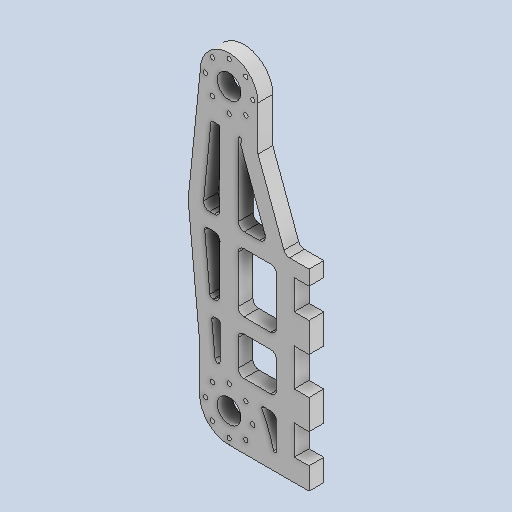
# Autodesk Inventor part: CalfSideL
Saved by Autodesk Inventor 2025.2 (Build 292293000, 293)
## iProperties
Created: 2025-06-24
Part Number: CalfSideL
Material: Generic
Document SubType Name: Modeling
Designer: ricoa
Density: 1 g/cm^3
Appearance: Default
Author: ricoa
Autodesk Inventor part; units mm, degrees
ref_plane "YZ Plane" through (0, 0, 0) normal (1, 0, 0) x (0, 1, 0)
ref_plane "XZ Plane" through (0, 0, 0) normal (0, 1, 0) x (-1, 0, 0)
ref_plane "XY Plane" through (0, 0, 0) normal (0, 0, 1) x (1, 0, 0)
sketch "Sketch1" plane through (0, 0, 0) normal (0, 0, 1) x (1, 0, 0)
  line L0 (-1.9363, -53.8484) -> (-0.1341, -49.1844) construction
  line L1 (-13.3705, 26.1501) -> (9.4827, 17.3195) construction
  circle A0 centre (0, 0) radius 4 projected
  circle A1 centre (-5.6569, 5.6569) radius 0.75 projected
  circle A2 centre (-8, 0) radius 0.75 projected
  circle A3 centre (-5.6569, -5.6569) radius 0.75 projected
  circle A4 centre (0, -8) radius 0.75 projected
  circle A5 centre (5.6569, -5.6569) radius 0.75 projected
  circle A6 centre (8, 0) radius 0.75 projected
  circle A7 centre (5.6569, 5.6569) radius 0.75 projected
  circle A8 centre (0, 8) radius 0.75 projected
  line L2 (0, 0) -> (0, -10)
  line L3 (75.6727, -5.2019) -> (75.6727, 49.7974) projected
  arc A9 (9.75, 94.9743) -> (-9.75, 95.0257) centre (0, 95) ccw
  circle A10 centre (0, 95) radius 4 projected
  circle A11 centre (-5.6569, 100.6569) radius 0.75 projected
  circle A12 centre (-8, 95) radius 0.75 projected
  circle A13 centre (-5.6569, 89.3431) radius 0.75 projected
  circle A14 centre (0, 87) radius 0.75 projected
  circle A15 centre (5.6569, 89.3431) radius 0.75 projected
  circle A16 centre (8, 95) radius 0.75 projected
  circle A17 centre (5.6569, 100.6569) radius 0.75 projected
  circle A18 centre (0, 103) radius 0.75 projected
  arc A19 (-9.9999, 0.0526) -> (0, -10) centre (0, 0) ccw
  line L4 (-10, 0) -> (-9.75, 95.0257) construction
  line L5 (-10, 0) -> (-9.9605, 14.9999)
  line L6 (9.75, 95.0257) -> (9.75, 80.4282)
  line L7 (-9.8553, 55) -> (-13.8553, 55) construction
  line L8 (-9.75, 95.0257) -> (-13.8349, 55.1989)
  line L9 (-13.8359, 54.801) -> (-9.9605, 14.9999)
  arc A20 (-13.8349, 55.1989) -> (-13.8359, 54.801) centre (-11.8453, 54.9948) ccw
  line L10 (0, -10) -> (15, -10)
  line L11 (15, -10) -> (27, -10)
  line L12 (27, -10) -> (27, 55)
  line L13 (27, 55) -> (20.393, 55)
  line L14 (9.75, 80.4282) -> (9.75, 80.0257)
  line L15 (18.517, 56.3066) -> (9.75, 80.0257)
  arc A21 (18.517, 56.3066) -> (20.393, 55) centre (20.393, 57) ccw
  line L16 (27, 55) -> (27, 50)
  line L17 (27, 50) -> (22, 50)
  line L18 (22, 50) -> (22, 40)
  line L19 (22, 40) -> (27, 40)
  line L20 (27, 40) -> (27, 30)
  line L21 (27, 30) -> (22, 30)
  line L22 (22, 30) -> (22, 17.4303)
  line L23 (22, 17.4303) -> (22, 27.4303)
  line L24 (22, 17.4303) -> (27, 17.4303)
  line L25 (27, 17.4303) -> (27, 7.4303)
  line L26 (27, 7.4303) -> (22, 7.4303)
  line L27 (22, 7.4303) -> (22, -2.5697)
  line L28 (22, -2.5697) -> (27, -2.5697)
  point P0 (19, 55)
  dimension "d20" = 10
  dimension "d22" = 15
  dimension "d23" = 15
  dimension "d25" = 4
  dimension "d27" = 15
  dimension "d28" = 12
  dimension "d29" = 65
  dimension "d30" = 8
  dimension "d31" = 2
  dimension "d32" = 5
  dimension "d33" = 5
  dimension "d34" = 10
  dimension "d35" = 10
  dimension "d36" = 10
  dimension "d37" = 10
  dimension "d38" = 10
  constraints: 52 end point, 19 point on line, 10 point on circle, 8 perpendicular, 5 tangent, 4 centre point, 4 vertical, 3 horizontal, 1 coincident
  measures "d20" distance of L2.start L2.end
  measures "d22" distance of L4.start L5.end
  measures "d23" distance of L6.start L14.end
  measures "d25" distance of L7.start L7.end
  measures "d27" distance of L2.end L10.end
  measures "d28" distance of L10.end L11.end
  measures "d29" distance of L11.end L12.end
  measures "d30" distance of L12.end point (19, 55)
  measures "d31" radius of A21
  measures "d32" distance of L12.end L16.end
  measures "d33" distance of L16.end L17.end
  measures "d34" distance of L17.end L18.end
  measures "d35" distance of L19.end L20.end
  measures "d36" distance of L22.end L23.end
  measures "d37" distance of L24.end L25.end
  measures "d38" distance of L26.end L27.end
extrude "Extrusion1" add sketch "Sketch1" along normal blind 5 contours L6 L14 L15 A21 L13 L12 L17 L18 L19 L21 L22 L24 L26 L27 L28 L11 L10 A19 L5 L9 A20 L8 A9
sketch "Sketch2" plane through (0, 0, 5) normal (0, 0, 1) x (1, 0, 0)
  line L0 (0, -10) -> (27, -10) projected
  line L1 (27, -10) -> (27, -2.5697) projected
  line L2 (27, -2.5697) -> (22, -2.5697) projected
  line L3 (22, -2.5697) -> (22, 7.4303) projected
  line L4 (22, 7.4303) -> (27, 7.4303) projected
  line L5 (27, 7.4303) -> (27, 17.4303) projected
  line L6 (27, 17.4303) -> (22, 17.4303) projected
  line L7 (22, 17.4303) -> (22, 30) projected
  line L8 (22, 30) -> (27, 30) projected
  line L9 (27, 30) -> (27, 40) projected
  line L10 (27, 40) -> (22, 40) projected
  line L11 (22, 40) -> (22, 50) projected
  line L12 (22, 50) -> (27, 50) projected
  line L13 (27, 50) -> (27, 55) projected
  line L14 (27, 55) -> (20.393, 55) projected
  arc A0 (18.517, 56.3066) -> (20.393, 55) centre (20.393, 57) ccw projected
  line L15 (18.517, 56.3066) -> (9.75, 80.0257) projected
  line L16 (9.75, 80.0257) -> (9.75, 95.0257) projected
  arc A1 (9.75, 95.0257) -> (-9.75, 95.0257) centre (0, 95) ccw projected
  line L17 (-9.75, 95.0257) -> (-13.8349, 55.1989) projected
  arc A2 (-13.8349, 55.1989) -> (-13.8359, 54.801) centre (-11.8453, 54.9948) ccw projected
  line L18 (-13.8359, 54.801) -> (-9.9605, 14.9999) projected
  line L19 (-9.9605, 14.9999) -> (-10, 0) projected
  arc A3 (-10, 0) -> (0, -10) centre (0, 0) ccw projected
  circle A4 centre (0, 0) radius 4 projected
  circle A5 centre (0, -8) radius 0.75 projected
  circle A6 centre (0, 87) radius 0.75 projected
  circle A7 centre (-5.6569, 5.6569) radius 0.75 projected
  circle A8 centre (5.6569, -5.6569) radius 0.75 projected
  circle A9 centre (8, 0) radius 0.75 projected
  circle A10 centre (5.6569, 5.6569) radius 0.75 projected
  circle A11 centre (0, 8) radius 0.75 projected
  circle A12 centre (-5.6569, 89.3431) radius 0.75 projected
  circle A13 centre (5.6569, 89.3431) radius 0.75 projected
  circle A14 centre (0, 103) radius 0.75 projected
  circle A15 centre (5.6569, 100.6569) radius 0.75 projected
  circle A16 centre (8, 95) radius 0.75 projected
  circle A17 centre (-8, 95) radius 0.75 projected
  circle A18 centre (-5.6569, 100.6569) radius 0.75 projected
  circle A19 centre (0, 95) radius 4 projected
  circle A20 centre (-5.6569, -5.6569) radius 0.75 projected
  circle A21 centre (-8, 0) radius 0.75 projected
  line L20 (3.9336, 79.8158) -> (12.1125, 57.6882)
  line L21 (10.2365, 54.9948) -> (5.108, 54.9948)
  line L22 (3.108, 56.9948) -> (3.108, 81.481)
  line L23 (4.1052, 81.4281) -> (3.9336, 79.8158)
  arc A22 (10.2365, 54.9948) -> (12.1125, 57.6882) centre (10.2365, 56.9948) ccw
  arc A23 (3.108, 56.9948) -> (5.108, 54.9948) centre (5.108, 56.9948) ccw
  arc A24 (4.1052, 81.4281) -> (3.108, 81.481) centre (3.608, 81.481) ccw
  line L24 (0, 87) -> (0, 0) construction
  line L25 (-9.75, 95.0257) -> (-13.8349, 55.1989) projected
  line L26 (-11.2885, 80.0257) -> (-6.2885, 80.0257)
  line L27 (-6.2885, 80.0257) -> (-8.6507, 56.9948)
  line L28 (-8.6507, 56.9948) -> (-8.6297, 57.1989)
  line L29 (-3.108, 56.9948) -> (-3.108, 81.481)
  line L30 (-3.108, 56.9948) -> (-3.108, 54.9948)
  line L31 (5.108, 54.9948) -> (3.108, 54.9948)
  line L32 (-5.108, 54.9948) -> (-6.6402, 54.9948)
  line L33 (-6.2885, 80.0257) -> (-6.1352, 81.5197)
  line L34 (-3.3913, 81.9687) -> (-5.6378, 81.9687)
  arc A25 (-5.6378, 81.9687) -> (-6.1352, 81.5197) centre (-5.6378, 81.4687) ccw
  line L35 (-3.3913, 81.9687) -> (-3.608, 81.9687)
  line L36 (-3.108, 81.4687) -> (-3.108, 81.481)
  arc A26 (-3.108, 81.4687) -> (-3.608, 81.9687) centre (-3.608, 81.4687) ccw
  arc A27 (-5.108, 54.9948) -> (-3.108, 56.9948) centre (-5.108, 56.9948) ccw
  arc A28 (-8.6297, 57.1989) -> (-6.6402, 54.9948) centre (-6.6402, 56.9948) ccw
  line L37 (16, 45) -> (16, 48)
  line L38 (14, 50) -> (5.0017, 50)
  line L39 (3.0017, 48) -> (3.0017, 32)
  line L40 (5.0017, 30) -> (14, 30)
  line L41 (16, 32) -> (16, 45)
  line L42 (-3.108, 54.9948) -> (-3.108, 50) construction
  line L43 (-3.108, 32) -> (-3.108, 48)
  line L44 (-5.5137, 30) -> (-5.108, 30)
  line L45 (-6.509, 30.9031) -> (-8.2616, 48.9031)
  line L46 (-7.2663, 50) -> (-5.108, 50)
  arc A29 (14, 30) -> (16, 32) centre (14, 32) ccw
  arc A30 (3.0017, 32) -> (5.0017, 30) centre (5.0017, 32) ccw
  arc A31 (16, 48) -> (14, 50) centre (14, 48) ccw
  arc A32 (5.0017, 50) -> (3.0017, 48) centre (5.0017, 48) ccw
  arc A33 (-3.108, 48) -> (-5.108, 50) centre (-5.108, 48) ccw
  arc A34 (-5.108, 30) -> (-3.108, 32) centre (-5.108, 32) ccw
  arc A35 (-6.465, 30.4515) -> (-5.9674, 30) centre (-5.9674, 30.5) ccw
  arc A36 (-7.8174, 50) -> (-8.315, 49.4515) centre (-7.8174, 49.5) ccw
  line L47 (5.0017, 25) -> (14, 25)
  line L48 (16, 23) -> (16, 14)
  line L49 (14, 12) -> (5.0017, 12)
  line L50 (3.0017, 14) -> (3.0017, 23)
  line L51 (-4.0017, 25) -> (-4.8628, 25)
  line L52 (-5.8579, 23.9009) -> (-4.7624, 12.9009)
  line L53 (-3.0017, 24) -> (-3.0017, 13)
  line L54 (-4.0017, 12) -> (-3.7673, 12)
  arc A37 (16, 23) -> (14, 25) centre (14, 23) ccw
  arc A38 (5.0017, 25) -> (3.0017, 23) centre (5.0017, 23) ccw
  arc A39 (3.0017, 14) -> (5.0017, 12) centre (5.0017, 14) ccw
  arc A40 (14, 12) -> (16, 14) centre (14, 14) ccw
  arc A41 (-3.0017, 24) -> (-4.0017, 25) centre (-4.0017, 24) ccw
  arc A42 (-4.8628, 25) -> (-5.8579, 23.9009) centre (-4.8628, 24) ccw
  arc A43 (-4.0017, 12) -> (-3.0017, 13) centre (-4.0017, 13) ccw
  arc A44 (-4.7624, 12.9009) -> (-3.7673, 12) centre (-3.7673, 13) ccw
  arc A45 (-6.509, 30.9031) -> (-5.5137, 30) centre (-5.5137, 31) ccw
  arc A46 (-7.2663, 50) -> (-8.2616, 48.9031) centre (-7.2663, 49) ccw
  line L55 (16, 12) -> (16, 7)
  line L56 (16, 5) -> (16, -3.9918)
  line L57 (5.6569, 7) -> (10.6569, 7)
  line L58 (8.75, 0) -> (13.75, 0)
  line L59 (16, -5) -> (16, -8.75)
  arc A47 (15.0163, -4.1184) -> (11.0394, 6.2712) centre (-34.1439, -16.9799) ccw
  arc A48 (15.0163, -4.1184) -> (16, -3.9918) centre (15.5, -3.9918) ccw
  line L60 (14, 7) -> (11.484, 7)
  arc A49 (16, 5) -> (14, 7) centre (14, 5) ccw
  arc A50 (11.484, 7) -> (11.0394, 6.2712) centre (11.484, 6.5) ccw
  point P0 (0, 0)
  point P1 (13.108, 54.9948)
  point P2 (-8.8558, 54.9948)
  point P3 (-4.1052, 81.4281)
  point P4 (3.0017, 50)
  point P5 (16, 30)
  point P6 (16, 25)
  point P7 (-3.108, 81.4687)
  point P8 (-3.8845, 12.0069)
  dimension "d62" = 10
  dimension "d63" = 2
  dimension "d64" = 0.5
  dimension "d65" = 5
  dimension "d69" = 0.5
  dimension "d70" = 0.5
  dimension "d71" = 2
  dimension "d75" = 2
  dimension "d76" = 0.5
  dimension "d78" = 13
  dimension "d79" = 2
  dimension "d80" = 1
  dimension "d83" = 5
  dimension "d84" = 12
  dimension "d85" = 5
  dimension "d86" = 5
  dimension "d87" = 0.5
  dimension "d88" = 2
  dimension "d89" = 0.5
  constraints: 80 end point, 61 point on circle, 56 tangent, 30 point on line, 29 centre point, 16 equal radius, 10 horizontal, 8 perpendicular, 8 vertical, 4 parallel, 3 symmetric about line, 1 collinear, 1 horizontal alignment, 1 other
  measures "d62" distance of L31.end point (13.108, 54.995)
  measures "d63" radius of A22
  measures "d64" radius of A24
  measures "d65" distance of L26.start L26.end
  measures "d69" radius of A25
  measures "d70" radius of A26
  measures "d71" radius of A27
  measures "d75" radius of A29
  measures "d76" radius of A35
  measures "d78" distance of point (16, 25) L55.start
  measures "d79" radius of A37
  measures "d80" radius of A41
  measures "d83" distance of L55.start L55.end
  measures "d84" distance of L55.end L59.start
  measures "d85" distance of L57.start L57.end
  measures "d86" distance of L58.start L58.end
  measures "d87" radius of A48
  measures "d88" radius of A49
  measures "d89" radius of A50
extrude "Extrusion2" cut sketch "Sketch2" against normal blind 5 contours L20 A22 L21 A23 L22 A24 L23 | L33 A25 L34 A26 L29 A27 L32 A28 L27 | L41 A29 L40 A30 L39 A32 L38 A31 L37 | A34 L44 A45 L45 A46 L46 A33 L43 | L47 A37 L48 A40 L49 A39 L50 A38 | A41 L53 A43 A44 L52 A42 L51 | L56 A48 A47 A50 L60 A49
body "Solid1"
